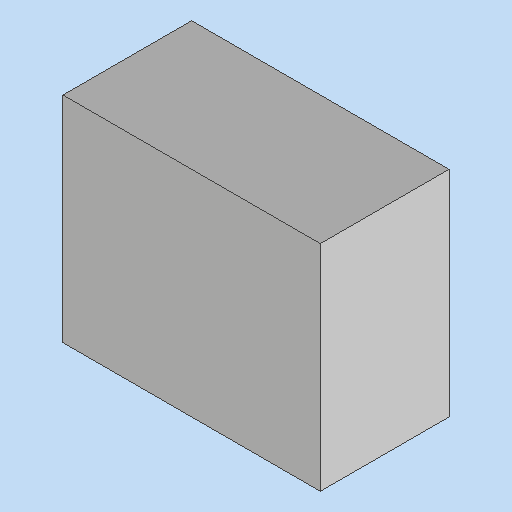
# Autodesk Inventor part: MM0988AN100_G02_152
Saved by Autodesk Inventor 2023.3 (Build 273359000, 359)
## iProperties
Created: 2025-08-29
Part Number: MM0988AN100_G02_152
Material: Generisch
Description: =<RBPARTNOTITLE2>
Vendor: Nanotec
Document SubType Name: Modellieren
Designer: RIC7AN
Mass: 6.336 g
Surface Area: 5.04 cm^2
Volume: 0.72 cm^3
Density: 8.8 g/cm^3
Sheet Metal Rule: Standard_mm
Appearance: Vorgabe
RBPARTMADEOF: ZK-NTO3-10-500-S
RBDRAWINGMISSINGSPEC: --
AnP_Kategorie: 2
RBPARTNOTITLE2: Encoderkabel
RBGBREMARKSINDEX: E
RBSURFACE: --
RBPARTNOTITLE1: encodercable
AnP_Material: =<Material>
RBMATERIAL: --
RBMATNO: =<Part Number>
RBPARTNO: SIEHE MNR
Author: RIC7AN
Keywords: =<RBPARTMADEOF>
Comments: =<RBSURFACE2>
Revision Number: 01
Autodesk Inventor part; units mm, degrees
ref_plane "YZ Plane" through (0, 0, 0) normal (1, 0, 0) x (0, 1, 0)
ref_plane "XZ Plane" through (0, 0, 0) normal (0, 1, 0) x (-1, 0, 0)
ref_plane "XY Plane" through (0, 0, 0) normal (0, 0, 1) x (1, 0, 0)
sketch "Skizze1" plane through (0, 0, 0) normal (0, 0, 1) x (1, 0, 0)
  line L0 (-6, 3) -> (6, 3)
  line L1 (6, 3) -> (6, -3)
  line L2 (6, -3) -> (-6, -3)
  line L3 (-6, -3) -> (-6, 3)
  line L4 (0, 4.2) -> (0, -4.2) projected
  line L5 (-8.4, 0) -> (8.4, 0) projected
  point P0 (0, 0)
  dimension "d0" = 6
  dimension "d1" = 12
  constraints: 8 end point, 2 parallel, 1 horizontal, 1 perpendicular, 2 other
  measures "d0" distance of L2.end L0.start
  measures "d1" distance of L0.start L0.end
extrude "Extrusion1" add sketch "Skizze1" along normal blind 10
equation "\"Biegeradius\" = 1.5 * Stärke"
equation "\"BreiteBiegungsfreistellung\" = Stärke"
equation "\"TiefeBiegungsfreistellung\" = 0.5 * Stärke"
equation "\"GrößeEckenfreistellung\" = 4 * Stärke"
equation "\"MinimalRest\" = 2 * Stärke"
equation "\"Übergangsradius\" = Biegeradius"
equation "\"JacobiRadiusGröße\" = Biegeradius"
equation "\"Abstandsgröße\" = Stärke"
equation "\"Stärke\" = 0.5"
